Autodesk Fusion 360 part; units mm, degrees
(part 2 of 6)
sketch "Sketch8" plane through (0, 0, 0) normal (0, 1, 0) x (-1, 0, 0)
  line L0 (96.56, 60.325) -> (94.4114, 75.5973)
  line L1 (94.4114, 75.5973) -> (80.5229, 127.4298)
  line L2 (80.5229, 127.4298) -> (-3.2035, 104.9953)
  line L3 (-3.2035, 104.9953) -> (-6.3109, 81.055)
  line L4 (-6.3109, 81.055) -> (-69.625, 81.055)
  line L5 (-69.625, 81.055) -> (-69.625, 62.005)
  line L6 (-69.625, 62.005) -> (-88.675, 62.005)
  line L7 (-88.675, 62.005) -> (-88.675, -58.195)
  line L8 (-88.675, -58.195) -> (-12.475, -58.195)
  line L9 (-12.475, -58.195) -> (-12.475, -67.72)
  line L10 (-12.475, -67.72) -> (6.575, -67.72)
  line L11 (6.575, -67.72) -> (6.575, -75.34)
  line L12 (6.575, -75.34) -> (50.575, -75.34)
  line L13 (50.575, -75.34) -> (50.575, -69.625)
  line L14 (50.575, -69.625) -> (96.56, -69.625)
  line L15 (96.56, -69.625) -> (96.56, 60.325)
  line L16 (17.9, 22.105) -> (1.15, 22.105)
  line L17 (1.15, 22.105) -> (1.15, 38.855)
  line L18 (1.15, 38.855) -> (17.9, 38.855)
  line L19 (17.9, 38.855) -> (17.9, 22.105)
  line L20 (-56, -6.47) -> (-56, 10.28)
  line L21 (-56, 10.28) -> (-39.25, 10.28)
  line L22 (-39.25, 10.28) -> (-39.25, -6.47)
  line L23 (-39.25, -6.47) -> (-56, -6.47)
  line L24 (17.9, -15.995) -> (1.15, -15.995)
  line L25 (1.15, -15.995) -> (1.15, 0.755)
  line L26 (1.15, 0.755) -> (17.9, 0.755)
  line L27 (17.9, 0.755) -> (17.9, -15.995)
  line L28 (-20.2, 50.68) -> (-36.95, 50.68)
  line L29 (-36.95, 50.68) -> (-36.95, 67.43)
  line L30 (-36.95, 67.43) -> (-20.2, 67.43)
  line L31 (-20.2, 67.43) -> (-20.2, 50.68)
  line L32 (75.05, -36.95) -> (58.3, -36.95)
  line L33 (58.3, -36.95) -> (58.3, -20.2)
  line L34 (58.3, -20.2) -> (75.05, -20.2)
  line L35 (75.05, -20.2) -> (75.05, -36.95)
  line L36 (-75.05, -6.47) -> (-75.05, 29.33)
  line L37 (-75.05, 29.33) -> (-58.3, 29.33)
  line L38 (-58.3, 29.33) -> (-58.3, -6.47)
  line L39 (-58.3, -6.47) -> (-75.05, -6.47)
  line L40 (-1.15, -25.52) -> (-17.9, -25.52)
  line L41 (-17.9, -25.52) -> (-17.9, -8.77)
  line L42 (-17.9, -8.77) -> (-1.15, -8.77)
  line L43 (-1.15, -8.77) -> (-1.15, -25.52)
  line L44 (20.2, -61.715) -> (20.2, -44.965)
  line L45 (20.2, -44.965) -> (36.95, -44.965)
  line L46 (36.95, -44.965) -> (36.95, -61.715)
  line L47 (36.95, -61.715) -> (20.2, -61.715)
  line L48 (56, 1.15) -> (39.25, 1.15)
  line L49 (39.25, 1.15) -> (39.25, 17.9)
  line L50 (39.25, 17.9) -> (56, 17.9)
  line L51 (56, 17.9) -> (56, 1.15)
  line L52 (-58.3, -44.57) -> (-75.05, -44.57)
  line L53 (-75.05, -44.57) -> (-75.05, -27.82)
  line L54 (-75.05, -27.82) -> (-58.3, -27.82)
  line L55 (-58.3, -27.82) -> (-58.3, -44.57)
  line L56 (-20.2, -6.47) -> (-36.95, -6.47)
  line L57 (-36.95, -6.47) -> (-36.95, 10.28)
  line L58 (-36.95, 10.28) -> (-20.2, 10.28)
  line L59 (-20.2, 10.28) -> (-20.2, -6.47)
  line L60 (20.2, 14.485) -> (20.2, 31.235)
  line L61 (20.2, 31.235) -> (36.95, 31.235)
  line L62 (36.95, 31.235) -> (36.95, 14.485)
  line L63 (36.95, 14.485) -> (20.2, 14.485)
  line L64 (-1.15, 31.63) -> (-17.9, 31.63)
  line L65 (-17.9, 31.63) -> (-17.9, 48.38)
  line L66 (-17.9, 48.38) -> (-1.15, 48.38)
  line L67 (-1.15, 48.38) -> (-1.15, 31.63)
  line L68 (17.9, -35.045) -> (1.15, -35.045)
  line L69 (1.15, -35.045) -> (1.15, -18.295)
  line L70 (1.15, -18.295) -> (17.9, -18.295)
  line L71 (17.9, -18.295) -> (17.9, -35.045)
  line L72 (56.3587, 69.7865) -> (52.0235, 85.9657)
  line L73 (52.0235, 85.9657) -> (68.2028, 90.3009)
  line L74 (68.2028, 90.3009) -> (72.538, 74.1217)
  line L75 (72.538, 74.1217) -> (56.3587, 69.7865)
  line L76 (1.15, -54.095) -> (1.15, -37.345)
  line L77 (1.15, -37.345) -> (17.9, -37.345)
  line L78 (17.9, -37.345) -> (17.9, -54.095)
  line L79 (17.9, -54.095) -> (1.15, -54.095)
  line L80 (20.2, -4.565) -> (20.2, 12.185)
  line L81 (20.2, 12.185) -> (36.95, 12.185)
  line L82 (36.95, 12.185) -> (36.95, -4.565)
  line L83 (36.95, -4.565) -> (20.2, -4.565)
  line L84 (75.05, 39.25) -> (36.95, 39.25)
  line L85 (36.95, 39.25) -> (36.95, 33.535)
  line L86 (36.95, 33.535) -> (20.2, 33.535)
  line L87 (20.2, 33.535) -> (20.2, 56)
  line L88 (20.2, 56) -> (75.05, 56)
  line L89 (75.05, 56) -> (75.05, 39.25)
  line L90 (17.9, 3.055) -> (1.15, 3.055)
  line L91 (1.15, 3.055) -> (1.15, 19.805)
  line L92 (1.15, 19.805) -> (17.9, 19.805)
  line L93 (17.9, 19.805) -> (17.9, 3.055)
  line L94 (17.9, 41.155) -> (1.15, 41.155)
  line L95 (1.15, 41.155) -> (1.15, 57.905)
  line L96 (1.15, 57.905) -> (17.9, 57.905)
  line L97 (17.9, 57.905) -> (17.9, 41.155)
  line L98 (20.2, -23.615) -> (20.2, -6.865)
  line L99 (20.2, -6.865) -> (36.95, -6.865)
  line L100 (36.95, -6.865) -> (36.95, -23.615)
  line L101 (36.95, -23.615) -> (20.2, -23.615)
  line L102 (-56, -44.57) -> (-56, -27.82)
  line L103 (-56, -27.82) -> (-39.25, -27.82)
  line L104 (-39.25, -27.82) -> (-39.25, -44.57)
  line L105 (-39.25, -44.57) -> (-56, -44.57)
  line L106 (51.4282, 88.1874) -> (47.093, 104.3666)
  line L107 (47.093, 104.3666) -> (63.2723, 108.7018)
  line L108 (63.2723, 108.7018) -> (67.6075, 92.5226)
  line L109 (67.6075, 92.5226) -> (51.4282, 88.1874)
  line L110 (-20.2, 31.63) -> (-36.95, 31.63)
  line L111 (-36.95, 31.63) -> (-36.95, 48.38)
  line L112 (-36.95, 48.38) -> (-20.2, 48.38)
  line L113 (-20.2, 48.38) -> (-20.2, 31.63)
  line L114 (-1.15, -6.47) -> (-17.9, -6.47)
  line L115 (-17.9, -6.47) -> (-17.9, 10.28)
  line L116 (-17.9, 10.28) -> (-1.15, 10.28)
  line L117 (-1.15, 10.28) -> (-1.15, -6.47)
  line L118 (-17.9, -44.57) -> (-17.9, -27.82)
  line L119 (-17.9, -27.82) -> (-1.15, -27.82)
  line L120 (-1.15, -27.82) -> (-1.15, -44.57)
  line L121 (-1.15, -44.57) -> (-17.9, -44.57)
  line L122 (56, -56) -> (39.25, -56)
  line L123 (39.25, -56) -> (39.25, -39.25)
  line L124 (39.25, -39.25) -> (56, -39.25)
  line L125 (56, -39.25) -> (56, -56)
  line L126 (75.05, -17.9) -> (58.3, -17.9)
  line L127 (58.3, -17.9) -> (58.3, -1.15)
  line L128 (58.3, -1.15) -> (75.05, -1.15)
  line L129 (75.05, -1.15) -> (75.05, -17.9)
  line L130 (-20.2, -25.52) -> (-36.95, -25.52)
  line L131 (-36.95, -25.52) -> (-36.95, -8.77)
  line L132 (-36.95, -8.77) -> (-20.2, -8.77)
  line L133 (-20.2, -8.77) -> (-20.2, -25.52)
  line L134 (-58.3, -25.52) -> (-75.05, -25.52)
  line L135 (-75.05, -25.52) -> (-75.05, -8.77)
  line L136 (-75.05, -8.77) -> (-58.3, -8.77)
  line L137 (-58.3, -8.77) -> (-58.3, -25.52)
  line L138 (-20.2, 12.58) -> (-36.95, 12.58)
  line L139 (-36.95, 12.58) -> (-36.95, 29.33)
  line L140 (-36.95, 29.33) -> (-20.2, 29.33)
  line L141 (-20.2, 29.33) -> (-20.2, 12.58)
  line L142 (-56, 50.68) -> (-56, 67.43)
  line L143 (-56, 67.43) -> (-39.25, 67.43)
  line L144 (-39.25, 67.43) -> (-39.25, 50.68)
  line L145 (-39.25, 50.68) -> (-56, 50.68)
  line L146 (37.9578, 64.856) -> (33.6226, 81.0352)
  line L147 (33.6226, 81.0352) -> (49.8019, 85.3704)
  line L148 (49.8019, 85.3704) -> (54.1371, 69.1912)
  line L149 (54.1371, 69.1912) -> (37.9578, 64.856)
  line L150 (-1.15, 12.58) -> (-17.9, 12.58)
  line L151 (-17.9, 12.58) -> (-17.9, 29.33)
  line L152 (-17.9, 29.33) -> (-1.15, 29.33)
  line L153 (-1.15, 29.33) -> (-1.15, 12.58)
  line L154 (-75.05, 31.63) -> (-75.05, 48.38)
  line L155 (-75.05, 48.38) -> (-39.25, 48.38)
  line L156 (-39.25, 48.38) -> (-39.25, 31.63)
  line L157 (-39.25, 31.63) -> (-75.05, 31.63)
  line L158 (56, 20.2) -> (39.25, 20.2)
  line L159 (39.25, 20.2) -> (39.25, 36.95)
  line L160 (39.25, 36.95) -> (56, 36.95)
  line L161 (56, 36.95) -> (56, 20.2)
  line L162 (58.3, -56) -> (58.3, -39.25)
  line L163 (58.3, -39.25) -> (75.05, -39.25)
  line L164 (75.05, -39.25) -> (75.05, -56)
  line L165 (75.05, -56) -> (58.3, -56)
  line L166 (14.6264, 78.3264) -> (10.2912, 94.5056)
  line L167 (10.2912, 94.5056) -> (26.4705, 98.8408)
  line L168 (26.4705, 98.8408) -> (30.8057, 82.6616)
  line L169 (30.8057, 82.6616) -> (14.6264, 78.3264)
  line L170 (33.0273, 83.2569) -> (28.6921, 99.4361)
  line L171 (28.6921, 99.4361) -> (44.8714, 103.7713)
  line L172 (44.8714, 103.7713) -> (49.2066, 87.5921)
  line L173 (49.2066, 87.5921) -> (33.0273, 83.2569)
  line L174 (-56, 12.58) -> (-56, 29.33)
  line L175 (-56, 29.33) -> (-39.25, 29.33)
  line L176 (-39.25, 29.33) -> (-39.25, 12.58)
  line L177 (-39.25, 12.58) -> (-56, 12.58)
  line L178 (56, -36.95) -> (39.25, -36.95)
  line L179 (39.25, -36.95) -> (39.25, -20.2)
  line L180 (39.25, -20.2) -> (56, -20.2)
  line L181 (56, -20.2) -> (56, -36.95)
  line L182 (75.05, 20.2) -> (58.3, 20.2)
  line L183 (58.3, 20.2) -> (58.3, 36.95)
  line L184 (58.3, 36.95) -> (75.05, 36.95)
  line L185 (75.05, 36.95) -> (75.05, 20.2)
  line L186 (-20.2, -44.57) -> (-36.95, -44.57)
  line L187 (-36.95, -44.57) -> (-36.95, -27.82)
  line L188 (-36.95, -27.82) -> (-20.2, -27.82)
  line L189 (-20.2, -27.82) -> (-20.2, -44.57)
  line L190 (75.05, 1.15) -> (58.3, 1.15)
  line L191 (58.3, 1.15) -> (58.3, 17.9)
  line L192 (58.3, 17.9) -> (75.05, 17.9)
  line L193 (75.05, 17.9) -> (75.05, 1.15)
  line L194 (-39.25, -25.52) -> (-56, -25.52)
  line L195 (-56, -25.52) -> (-56, -8.77)
  line L196 (-56, -8.77) -> (-39.25, -8.77)
  line L197 (-39.25, -8.77) -> (-39.25, -25.52)
  line L198 (19.5569, 59.9255) -> (15.2217, 76.1047)
  line L199 (15.2217, 76.1047) -> (31.401, 80.4399)
  line L200 (31.401, 80.4399) -> (35.7362, 64.2607)
  line L201 (35.7362, 64.2607) -> (19.5569, 59.9255)
  line L202 (20.2, -42.665) -> (20.2, -25.915)
  line L203 (20.2, -25.915) -> (36.95, -25.915)
  line L204 (36.95, -25.915) -> (36.95, -42.665)
  line L205 (36.95, -42.665) -> (20.2, -42.665)
  line L206 (56, -17.9) -> (39.25, -17.9)
  line L207 (39.25, -17.9) -> (39.25, -1.15)
  line L208 (39.25, -1.15) -> (56, -1.15)
  line L209 (56, -1.15) -> (56, -17.9)
  line L210 (-1.15, 50.68) -> (-17.9, 50.68)
  line L211 (-17.9, 50.68) -> (-17.9, 67.43)
  line L212 (-17.9, 67.43) -> (-1.15, 67.43)
  line L213 (-1.15, 67.43) -> (-1.15, 50.68)
  line L214 (65.8355, 113.1415) -> (5.7914, 97.0528)
  line L215 (2.475, 71.055) -> (-59.625, 71.055)
  line L216 (-59.625, 71.055) -> (-59.625, 52.005)
  line L217 (-59.625, 52.005) -> (-78.675, 52.005)
  line L218 (-78.675, 52.005) -> (-78.675, -48.195)
  line L219 (-78.675, -48.195) -> (-2.475, -48.195)
  line L220 (-2.475, -48.195) -> (-2.475, -57.72)
  line L221 (-2.475, -57.72) -> (16.575, -57.72)
  line L222 (16.575, -57.72) -> (16.575, -65.34)
  line L223 (16.575, -65.34) -> (40.575, -65.34)
  line L224 (40.575, -65.34) -> (40.575, -59.625)
  line L225 (40.575, -59.625) -> (78.8, -59.625)
  line L226 (1.15, 57.905) -> (1.15, 61.655) construction
  line L227 (1.15, 61.655) -> (15.25, 61.655) construction
  line L228 (2.475, 71.055) -> (2.475, 61.655)
  line L229 (5.7914, 97.0528) -> (15.25, 61.655)
  line L230 (15.25, 61.655) -> (2.475, 61.655)
  line L231 (72.538, 74.1217) -> (73.5085, 70.4995) construction
  line L232 (33.391, 56) -> (33.391, 59.75) construction
  line L233 (32.4204, 63.3722) -> (33.391, 59.75) construction
  line L234 (73.4519, 115.1823) -> (65.8355, 113.1415) construction
  line L235 (65.8355, 113.1415) -> (76.9777, 71.5584)
  line L236 (76.9777, 71.5584) -> (33.391, 59.75)
  line L237 (75.05, 56) -> (78.8, 56) construction
  line L238 (78.8, 56) -> (78.8, 59.75) construction
  line L239 (33.391, 59.75) -> (78.8, 59.75)
  line L240 (78.8, 59.75) -> (78.8, -59.625)
  dimension "d208" = 3.75
  dimension "d209" = 14.1
  dimension "d210" = 3.75
  dimension "d211" = 3.75
  dimension "d212" = 3.75
  dimension "d213" = 7.885
  dimension "d214" = 43.05
  dimension "d215" = 3.75
  dimension "d216" = 3.75
  dimension "d217" = 10
  dimension "d218" = 10
  dimension "d219" = 10
  dimension "d220" = 10
  dimension "d221" = 10
  dimension "d222" = 10
  dimension "d223" = 10
  dimension "d224" = 10
  dimension "d225" = 10
  dimension "d226" = 10
  dimension "d227" = 10
  dimension "d228" = 10
  constraint coincident L95.end L96.start
  constraint perpendicular L96 L226
  constraint perpendicular L95 L227
  constraint coincident L227 L228.end
  constraint perpendicular L227 L228
  constraint coincident L74.end L75.start
  constraint perpendicular L75 L231
  constraint coincident L88 L232.start
  constraint perpendicular L88 L232
  constraint coincident L201 L233.start
  constraint perpendicular L201 L233
  constraint coincident L232.end L233.end
  constraint perpendicular L234 L235
  constraint coincident L88.end L89.start
  constraint perpendicular L89 L237
  constraint perpendicular L237 L238
  constraint perpendicular L225 L240
  measures "d208" distance of L95.end L226.end
  measures "d209" distance of L226.end L227.end
  measures "d210" distance of L74.end L231.end
  measures "d211" distance of L232.start L232.end
  measures "d212" distance of L233.start L232.end
  measures "d213" distance of L234.start L214.start
  measures "d214" distance of L214.start L235.end
  measures "d215" distance of L88.end L237.end
  measures "d216" distance of L237.end L238.end
  measures "d217" distance of L2 L214
  measures "d218" distance of L4 L215
  measures "d219" distance of L5 L216
  measures "d220" distance of L6 L217
  measures "d221" distance of L7 L218
  measures "d222" distance of L8 L219
  measures "d223" distance of L9 L220
  measures "d224" distance of L10 L221
  measures "d225" distance of L11 L222
  measures "d226" distance of L12 L223
  measures "d227" distance of L13 L224
  measures "d228" distance of L14 L225
extrude "Extrude5" add sketch "Sketch8" along normal blind 2.5 contours L0 L1 L2 L3 L4 L5 L6 L7 L8 L9 L10 L11 L12 L13 L14 L15
fillet "Fillet1" radius 1.5 19 edges at (-33.391, 1.25, 59.75) (-76.9777, 1.25, 71.5584) (-78.8, 1.25, 59.75) (-65.8355, 1.25, 113.1415) (-15.25, 1.25, 61.655) (-2.475, 1.25, 61.655) (-2.475, 1.25, 71.055) (-5.7914, 1.25, 97.0528) (59.625, 1.25, 71.055) (59.625, 1.25, 52.005) (78.675, 1.25, 52.005) (78.675, 1.25, -48.195) (2.475, 1.25, -48.195) (2.475, 1.25, -57.72) (-16.575, 1.25, -57.72) (-40.575, 1.25, -65.34) (-16.575, 1.25, -65.34) (-40.575, 1.25, -59.625) (-78.8, 1.25, -59.625)
fillet "Fillet2" radius 1 38 edges at (-43.1771, 2.5, 61.0522) (-60.982, 2.5, 59.75) (-78.3607, 2.5, 59.3107) (-78.8, 2.5, 0.0625) (-78.3607, 2.5, -59.1857) (-59.6875, 2.5, -59.625) (-41.0143, 2.5, -60.0643) (-40.575, 2.5, -62.4825) (-40.1357, 2.5, -64.9007) (-28.575, 2.5, -65.34) (-17.0143, 2.5, -64.9007) (-16.575, 2.5, -61.53) (-16.1357, 2.5, -58.1593) (-7.05, 2.5, -57.72) (2.0357, 2.5, -57.2807) (2.475, 2.5, -52.9575) (2.9143, 2.5, -48.6343) (40.575, 2.5, -48.195) (78.2357, 2.5, -47.7557) (78.675, 2.5, 1.905) (78.2357, 2.5, 51.5657) (69.15, 2.5, 52.005) (60.0643, 2.5, 52.4443) (59.625, 2.5, 61.53) (59.1857, 2.5, 70.6157) (28.575, 2.5, 71.055) (-2.0357, 2.5, 70.6157) (-2.475, 2.5, 66.355) (-2.9143, 2.5, 62.0943) (-8.6358, 2.5, 61.655) (-14.4863, 2.5, 62.2414) (-10.462, 2.5, 79.5734) (-6.3287, 2.5, 96.7423) (-35.813, 2.5, 105.097) (-65.5249, 2.5, 112.6035) (-71.4072, 2.5, 92.348) (-76.4417, 2.5, 71.8669) (-59.9028, 2.5, 66.9325)
sketch "Sketch9" plane through (0, -4, 0) normal (0, -1, 0) x (1, 0, 0)
  line L0 (-96.56, -49.625) -> (-86.56, -49.625)
  line L1 (-86.56, -49.625) -> (-86.56, 59.625)
  line L2 (-86.56, 59.625) -> (-84.594, 73.5992)
  line L3 (-84.594, 73.5992) -> (-76.04, 105.5231)
  line L4 (-76.04, 105.5231) -> (-85.6993, 108.1113)
  line L5 (-85.6993, 108.1113) -> (-94.4114, 75.5973)
  line L6 (-94.4114, 75.5973) -> (-96.56, 60.325)
  line L7 (-96.56, 60.325) -> (-96.56, -49.625)
  line L8 (-84.594, 73.5992) -> (-94.2533, 76.1874) construction
  line L9 (-89.4236, 74.8933) -> (-80.8697, 106.8172) construction
  circle A0 centre (-85.1466, 90.8552) radius 1.25
  line L10 (-86.56, 59.625) -> (-96.56, 59.625) construction
  line L11 (-91.56, -49.625) -> (-91.56, 59.625) construction
  line L12 (-91.56, -49.625) -> (-145.9994, 68.1019) construction
  circle A1 centre (-91.56, -49.625) radius 30 construction
  circle A2 centre (-104.1516, -22.3954) radius 30 construction
  circle A3 centre (-116.7431, 4.8343) radius 30 construction
  circle A4 centre (-129.3347, 32.0639) radius 30 construction
  line L13 (-129.3347, 32.0639) -> (-91.56, 59.625) construction
  line L14 (-116.7431, 4.8343) -> (-105.0997, 49.7462) construction
  circle A5 centre (-104.1516, -22.3954) radius 46.3967 construction
  circle A6 centre (-91.56, -49.625) radius 46.3967 construction
  line L15 (-91.56, -49.625) -> (-133.6722, -69.0986) construction
  line L16 (-104.1516, -22.3954) -> (-150.1994, -28.0744) construction
  line L17 (-116.7431, 4.8343) -> (-92.5081, 22.5166) construction
  line L18 (-92.5081, 22.5166) -> (-80.406, 31.3465) construction
  line L19 (-104.1516, -22.3954) -> (-79.9165, -4.7131) construction
  circle A7 centre (-91.56, -13.2083) radius 1.25
  circle A8 centre (-91.56, 23.2083) radius 1.25
  dimension "d235" = 2.5
  dimension "d236" = 60
  dimension "d237" = 2.5
  dimension "d238" = 2.5
  constraint coincident L2.end L3.start
  constraint coincident L5 L8.end
  constraint perpendicular L5 L8
  constraint midpoint L8 L9.start
  constraint midpoint L4 L9.end
  constraint midpoint L9 A0.centre
  constraint coincident L1.end L2.start
  constraint coincident L7 L10.end
  constraint perpendicular L7 L10
  constraint midpoint L0 L11.start
  constraint midpoint L10 L11.end
  constraint coincident L11.start L12.start
  constraint coincident A1 A2.centre
  constraint coincident L12 A2.centre
  constraint coincident L11.start A2
  constraint coincident A2 A3.centre
  constraint coincident L12 A3.centre
  constraint coincident A2.centre A3
  constraint coincident A3 A4.centre
  constraint coincident L12 A4.centre
  constraint coincident A3.centre A4
  constraint coincident A4.centre L13.start
  constraint coincident A3.centre L14.start
  constraint coincident A4 L14.end
  constraint coincident L13 L14.end
  constraint concentric A2 A5
  constraint coincident A6 L15.end
  constraint tangent A2 L15
  constraint coincident A2.centre A5.centre
  constraint coincident A5 L16.end
  constraint equal L14 L15
  constraint equal L14 L16
  constraint coincident A3 L17.end
  constraint coincident A5 L17.end
  constraint perpendicular A3 L18
  constraint coincident A6 L19.end
  constraint coincident A2 L19.end
  constraint coincident L19 A7.centre
  constraint coincident L11 A7.centre
  constraint coincident L18 A8.centre
  constraint coincident L11 A8.centre
  measures "d235" diameter of A0
  measures "d236" diameter of A1
  measures "d237" diameter of A7
  measures "d238" diameter of A8
sketch "Sketch10" plane through (0, -4, 0) normal (0, -1, 0) x (1, 0, 0)
  line L0 (78.675, -38.195) -> (88.675, -38.195)
  line L1 (88.675, -38.195) -> (88.675, 52.005)
  line L2 (88.675, 52.005) -> (78.675, 52.005)
  line L3 (78.675, 52.005) -> (78.675, -38.195)
  line L4 (83.675, -38.195) -> (83.675, 52.005) construction
  line L5 (83.675, -38.195) -> (131.5934, 61.3781) construction
  circle A0 centre (83.675, -38.195) radius 30 construction
  circle A1 centre (96.6841, -11.1624) radius 30 construction
  circle A2 centre (109.6933, 15.8702) radius 30 construction
  circle A3 centre (122.7024, 42.9029) radius 30 construction
  line L6 (122.7024, 42.9029) -> (83.675, 52.005) construction
  line L7 (109.6933, 15.8702) -> (93.4865, 49.7167) construction
  circle A4 centre (96.6841, -11.1624) radius 37.5266 construction
  circle A5 centre (83.675, -38.195) radius 37.5266 construction
  line L8 (83.675, -38.195) -> (115.208, -58.5399) construction
  line L9 (96.6841, -11.1624) -> (128.2172, -31.5072) construction
  line L10 (80.4773, 22.6841) -> (109.6933, 15.8702) construction
  line L11 (96.6841, -11.1624) -> (67.4682, -4.3485) construction
  circle A6 centre (83.675, -8.1283) radius 1.25
  circle A7 centre (83.675, 21.9383) radius 1.25
  dimension "d239" = 60
  dimension "d240" = 2.5
  dimension "d241" = 2.5
  constraint midpoint L0 L4.start
  constraint midpoint L2 L4.end
  constraint coincident L4.start L5.start
  constraint coincident A0 A1.centre
  constraint coincident L5 A1.centre
  constraint coincident L4.start A1
  constraint coincident A1 A2.centre
  constraint coincident L5 A2.centre
  constraint coincident A1.centre A2
  constraint coincident A2 A3.centre
  constraint coincident L5 A3.centre
  constraint coincident A2.centre A3
  constraint coincident A3.centre L6.start
  constraint coincident A2.centre L7.start
  constraint coincident L6 L7.end
  constraint coincident A3 L7.end
  constraint concentric A1 A4
  constraint concentric A0 A5
  constraint coincident A5 L8.end
  constraint coincident A1.centre A4.centre
  constraint coincident A4 L9.end
  constraint parallel L8 L9
  constraint equal L7 L9
  constraint equal L7 L8
  constraint coincident A2 L10.start
  constraint coincident A4 L10.start
  constraint coincident A5 L11.end
  constraint coincident A1 L11.end
  constraint coincident L11 A6.centre
  constraint coincident L4 A6.centre
  constraint coincident L10 A7.centre
  constraint coincident L4 A7.centre
  measures "d239" diameter of A0
  measures "d240" diameter of A6
  measures "d241" diameter of A7
sketch "Sketch11" plane through (0, -4, 0) normal (0, -1, 0) x (1, 0, 0)
  line L0 (-76.56, -59.625) -> (-76.56, -69.625)
  line L1 (-76.56, -69.625) -> (-50.575, -69.625)
  line L2 (-50.575, -69.625) -> (-50.575, -75.34)
  line L3 (-50.575, -75.34) -> (-6.575, -75.34)
  line L4 (-6.575, -75.34) -> (-6.575, -67.72)
  line L5 (-6.575, -67.72) -> (12.475, -67.72)
  line L6 (12.475, -67.72) -> (12.475, -58.195)
  line L7 (12.475, -58.195) -> (68.675, -58.195)
  line L8 (68.675, -58.195) -> (68.675, -48.195)
  line L9 (68.675, -48.195) -> (2.475, -48.195)
  line L10 (2.475, -48.195) -> (2.475, -57.72)
  line L11 (2.475, -57.72) -> (-16.575, -57.72)
  line L12 (-16.575, -57.72) -> (-16.575, -65.34)
  line L13 (-16.575, -65.34) -> (-40.575, -65.34)
  line L14 (-40.575, -65.34) -> (-40.575, -59.625)
  line L15 (-40.575, -59.625) -> (-76.56, -59.625)
  line L16 (12.475, -58.195) -> (2.475, -48.195) construction
  line L17 (7.475, -53.195) -> (68.675, -53.195) construction
  circle A0 centre (38.075, -53.195) radius 1.25
  line L18 (-28.575, -75.34) -> (-28.575, -65.34) construction
  circle A1 centre (-28.575, -70.34) radius 1.25
  dimension "d242" = 2.5
  dimension "d243" = 2.5
  constraint coincident L6.end L7.start
  constraint coincident L9.end L10.start
  constraint midpoint L16 L17.start
  constraint midpoint L8 L17.end
  constraint midpoint L17 A0.centre
  constraint midpoint L3 L18.start
  constraint midpoint L13 L18.end
  constraint midpoint L18 A1.centre
  measures "d242" diameter of A0
  measures "d243" diameter of A1
sketch "Sketch12" plane through (0, -4, 0) normal (0, -1, 0) x (1, 0, 0)
  line L0 (-61.2044, 122.2534) -> (-63.7926, 112.5941)
  line L1 (-63.7926, 112.5941) -> (-5.8515, 97.0689)
  line L2 (-5.8515, 97.0689) -> (-2.475, 71.055)
  line L3 (-2.475, 71.055) -> (59.625, 71.055)
  line L4 (59.625, 71.055) -> (59.625, 81.055)
  line L5 (59.625, 81.055) -> (6.3109, 81.055)
  line L6 (6.3109, 81.055) -> (3.2035, 104.9953)
  line L7 (3.2035, 104.9953) -> (-61.2044, 122.2534)
  line L8 (-2.475, 71.055) -> (6.3109, 81.055) construction
  line L9 (-5.8515, 97.0689) -> (3.2035, 104.9953) construction
  line L10 (-34.8293, 104.8334) -> (-32.2411, 114.4927) construction
  line L11 (4.7572, 93.0252) -> (-4.1633, 84.0619) construction
  line L12 (0.297, 88.5436) -> (-33.5352, 109.6631) construction
  line L13 (-16.6191, 99.1033) -> (3.2035, 104.9953) construction
  line L14 (-6.7078, 102.0493) -> (-1.324, 101.0321) construction
  line L15 (-6.7078, 102.0493) -> (-3.868, 98.8052) construction
  line L16 (-3.868, 98.8052) -> (-1.324, 101.0321) construction
  circle A0 centre (-2.596, 99.9186) radius 1.25
  line L17 (1.918, 76.055) -> (59.625, 76.055) construction
  circle A1 centre (30.7715, 76.055) radius 1.25
  line L18 (-34.8293, 104.8334) -> (-5.8515, 97.0689) construction
  dimension "d244" = 2.5
  dimension "d245" = 2.5
  dimension "d260" = 30
  constraint coincident L2.end L3.start
  constraint coincident L5.end L6.start
  constraint coincident L1.end L2.start
  constraint coincident L6.end L7.start
  constraint coincident L7 L10.end
  constraint perpendicular L7 L10
  constraint midpoint L6 L11.start
  constraint midpoint L2 L11.end
  constraint midpoint L11 L12.start
  constraint midpoint L10 L12.end
  constraint midpoint L12 L13.start
  constraint midpoint L13 L14.start
  constraint midpoint L9 L14.end
  constraint coincident L9 L15.end
  constraint perpendicular L9 L15
  constraint midpoint L16 A0.centre
  constraint midpoint L8 L17.start
  constraint midpoint L4 L17.end
  constraint midpoint L17 A1.centre
  constraint perpendicular L10 L18
  measures "d244" diameter of A0
  measures "d245" diameter of A1
  measures "d260" distance of L1.end L10.start
extrude "Extrude6" add sketch "Sketch12" sketch "Sketch9" sketch "Sketch11" sketch "Sketch10" along normal blind 5 contours A0 | A1 of sketch 2 contours A0 | A7 | A8 of sketch 3 contours A0 | A1 of sketch 4 contours A6 | A7
fillet "Fillet3" radius 1.25 9 edges at (29.6061, -9, 75.603) (-3.7614, -9, 99.4666) (-86.3121, -9, 90.4032) (-92.7254, -9, 22.7563) (-92.7254, -9, -13.6604) (-29.7404, -9, -70.792) (36.9096, -9, -53.647) (82.5096, -9, -8.5804) (82.5096, -9, 21.4863)
fillet "Fillet4" radius 1 198 edges at (-72.538, -0.75, 74.1217) (-54.1371, -0.75, 69.1912) (-35.7362, -0.75, 64.2607) (-30.8057, -0.75, 82.6616) (-49.2066, -0.75, 87.5921) (-67.6075, -0.75, 92.5226) (-56.3587, -0.75, 69.7865) (-51.4282, -0.75, 88.1874) (-33.0273, -0.75, 83.2569) (-19.5569, -0.75, 59.9255) (-37.9578, -0.75, 64.856) (-14.6264, -0.75, 78.3264) (-10.2912, -0.75, 94.5056) (-47.093, -0.75, 104.3666) (-28.6921, -0.75, 99.4361) (-52.0235, -0.75, 85.9657) (-33.6226, -0.75, 81.0352) (-15.2217, -0.75, 76.1047) (-26.4705, -0.75, 98.8408) (-31.401, -0.75, 80.4399) (-49.8019, -0.75, 85.3704) (-44.8714, -0.75, 103.7713) (-63.2723, -0.75, 108.7018) (-68.2028, -0.75, 90.3009) (-20.2, -0.75, 56) (-20.2, -0.75, 33.535) (-36.95, -0.75, 39.25) (-36.95, -0.75, 33.535) (-75.05, -0.75, 39.25) (-75.05, -0.75, 56) (-75.05, -0.75, 20.2) (-75.05, -0.75, 1.15) (-75.05, -0.75, -17.9) (-75.05, -0.75, -36.95) (-56, -0.75, -36.95) (-56, -0.75, -17.9) (-56, -0.75, 1.15) (-56, -0.75, 20.2) (-75.05, -0.75, -56) (-56, -0.75, -56) (-36.95, -0.75, -61.715) (-17.9, -0.75, -54.095) (-17.9, -0.75, -35.045) (-36.95, -0.75, -42.665) (-17.9, -0.75, -15.995) (-36.95, -0.75, -23.615) (-36.95, -0.75, -4.565) (-36.95, -0.75, 14.485) (-17.9, -0.75, 22.105) (-17.9, -0.75, 3.055) (-17.9, -0.75, 41.155) (1.15, -0.75, 50.68) (39.25, -0.75, 50.68) (20.2, -0.75, 50.68) (39.25, -0.75, 31.63) (20.2, -0.75, 31.63) (1.15, -0.75, 31.63) (1.15, -0.75, 12.58) (20.2, -0.75, 12.58) (39.25, -0.75, 12.58) (58.3, -0.75, -6.47) (39.25, -0.75, -6.47) (20.2, -0.75, -6.47) (1.15, -0.75, -6.47) (1.15, -0.75, -25.52) (1.15, -0.75, -44.57) (20.2, -0.75, -44.57) (20.2, -0.75, -25.52) (39.25, -0.75, -25.52) (39.25, -0.75, -44.57) (58.3, -0.75, -44.57) (58.3, -0.75, -25.52) (-39.25, -0.75, 20.2) (-58.3, -0.75, 20.2) (-39.25, -0.75, 1.15) (-58.3, -0.75, 1.15) (-20.2, -0.75, 14.485) (-20.2, -0.75, -4.565) (-20.2, -0.75, -23.615) (-39.25, -0.75, -17.9) (-58.3, -0.75, -17.9) (-58.3, -0.75, -36.95) (-39.25, -0.75, -36.95) (-20.2, -0.75, -42.665) (-20.2, -0.75, -61.715) (-39.25, -0.75, -56) (-58.3, -0.75, -56) (-1.15, -0.75, -54.095) (17.9, -0.75, -44.57) (-1.15, -0.75, -35.045) (17.9, -0.75, -25.52) (-1.15, -0.75, -15.995) (17.9, -0.75, -6.47) (-1.15, -0.75, 3.055) (17.9, -0.75, 12.58) (-1.15, -0.75, 22.105) (17.9, -0.75, 31.63) (-1.15, -0.75, 41.155) (17.9, -0.75, 50.68) (36.95, -0.75, 50.68) (56, -0.75, 50.68) (75.05, -0.75, 31.63) (36.95, -0.75, 31.63) (56, -0.75, 12.58) (36.95, -0.75, 12.58) (75.05, -0.75, -6.47) (56, -0.75, -6.47) (36.95, -0.75, -6.47) (36.95, -0.75, -25.52) (56, -0.75, -25.52) (75.05, -0.75, -25.52) (75.05, -0.75, -44.57) (56, -0.75, -44.57) (36.95, -0.75, -44.57) (75.05, -0.75, -27.82) (56, -0.75, -27.82) (36.95, -0.75, -27.82) (36.95, -0.75, -8.77) (56, -0.75, -8.77) (75.05, -0.75, -8.77) (75.05, -0.75, 29.33) (56, -0.75, 10.28) (56, -0.75, 29.33) (36.95, -0.75, 29.33) (36.95, -0.75, 10.28) (17.9, -0.75, -27.82) (17.9, -0.75, -8.77) (17.9, -0.75, 10.28) (17.9, -0.75, 29.33) (36.95, -0.75, 48.38) (75.05, -0.75, 48.38) (56, -0.75, 67.43) (36.95, -0.75, 67.43) (17.9, -0.75, 67.43) (17.9, -0.75, 48.38) (-1.15, -0.75, 57.905) (-1.15, -0.75, 38.855) (-1.15, -0.75, 19.805) (-1.15, -0.75, 0.755) (-1.15, -0.75, -18.295) (-1.15, -0.75, -37.345) (-20.2, -0.75, -44.965) (-20.2, -0.75, -25.915) (-20.2, -0.75, -6.865) (-20.2, -0.75, 12.185) (-20.2, -0.75, 31.235) (-39.25, -0.75, 36.95) (-39.25, -0.75, 17.9) (-58.3, -0.75, 36.95) (-58.3, -0.75, 17.9) (-39.25, -0.75, -1.15) (-58.3, -0.75, -1.15) (-58.3, -0.75, -20.2) (-39.25, -0.75, -20.2) (-39.25, -0.75, -39.25) (-58.3, -0.75, -39.25) (58.3, -0.75, -27.82) (58.3, -0.75, -8.77) (39.25, -0.75, -8.77) (39.25, -0.75, -27.82) (20.2, -0.75, -8.77) (20.2, -0.75, -27.82) (1.15, -0.75, -8.77) (1.15, -0.75, -27.82) (1.15, -0.75, 10.28) (20.2, -0.75, 10.28) (39.25, -0.75, 10.28) (58.3, -0.75, 29.33) (39.25, -0.75, 29.33) (20.2, -0.75, 29.33) (1.15, -0.75, 29.33) (1.15, -0.75, 48.38) (20.2, -0.75, 48.38) (39.25, -0.75, 48.38) (39.25, -0.75, 67.43) (20.2, -0.75, 67.43) (1.15, -0.75, 67.43) (-17.9, -0.75, 57.905) (-17.9, -0.75, 38.855) (-36.95, -0.75, 31.235) (-17.9, -0.75, 19.805) (-36.95, -0.75, 12.185) (-17.9, -0.75, 0.755) (-36.95, -0.75, -6.865) (-17.9, -0.75, -18.295) (-36.95, -0.75, -25.915) (-17.9, -0.75, -37.345) (-36.95, -0.75, -44.965) (-56, -0.75, -39.25) (-56, -0.75, -20.2) (-75.05, -0.75, -20.2) (-75.05, -0.75, -39.25) (-56, -0.75, -1.15) (-75.05, -0.75, -1.15) (-56, -0.75, 17.9) (-56, -0.75, 36.95) (-75.05, -0.75, 36.95) (-75.05, -0.75, 17.9)
fillet "Fillet5" radius 2.5 14 edges at (-80.5229, -2.35, 127.4298) (-96.56, -2.35, -69.625) (-50.575, -0.75, -69.625) (-50.575, -0.75, -75.34) (-6.575, -0.75, -75.34) (12.475, -0.75, -67.72) (12.475, -0.75, -58.195) (88.675, -2.35, -58.195) (-6.575, -0.75, -67.72) (3.2035, -0.75, 104.9953) (6.3109, -0.75, 81.055) (69.625, -2.35, 81.055) (69.625, -2.35, 62.005) (88.675, -2.35, 62.005)
fillet "Fillet6" radius 120 2 edges at (-96.56, -0.75, 60.325) (-94.4114, -0.75, 75.5973)
fillet "Fillet7" radius 0.5 30 edges at (2.8209, 2.5, 104.6604) (4.7236, 2.5, 93.2844) (6.8573, 2.5, 81.6769) (37.8162, 2.5, 81.055) (68.8928, 2.5, 80.3228) (69.625, 2.5, 71.53) (70.3572, 2.5, 62.7372) (79.15, 2.5, 62.005) (87.9428, 2.5, 61.2728) (88.675, 2.5, 1.905) (87.9428, 2.5, -57.4628) (50.575, 2.5, -58.195) (13.2072, 2.5, -58.9272) (12.475, 2.5, -62.9575) (11.7428, 2.5, -66.9878) (2.95, 2.5, -67.72) (-5.8428, 2.5, -68.4522) (-6.575, 2.5, -71.53) (-7.3072, 2.5, -74.6078) (-28.575, 2.5, -75.34) (-49.8428, 2.5, -74.6078) (-50.575, 2.5, -72.4825) (-51.3072, 2.5, -70.3572) (-73.5675, 2.5, -69.625) (-95.8278, 2.5, -68.8928) (-96.56, 2.5, -7.6724) (-95.5334, 2.5, 67.4434) (-86.8205, 2.5, 103.9267) (-80.0051, 2.5, 126.533) (-38.2606, 2.5, 116.1056)
equation "sw_size_Ref_Ref = 19.05 mm"
equation "sw_cut_size_Ref_Ref = 14 mm"
equation "sw_cut_space_Ref_Ref = sw_size_Ref_Ref - sw_cut_size_Ref_Ref"
equation "stab_cut_length_Ref_Ref = 6 mm"
equation "stab_cut_height_Ref_Ref = 12.5 mm"
equation "stabw_length_Ref_Ref = 12 mm" comment "Length of the stabilizer wire per unit (e.g. a 2u stabilizer will be stabilizer_wire_length * 2)"
equation "stabw_height_Ref_Ref = 2.5 mm"
equation "stabw_cut_length_Ref_Ref = 1.7 mm"
equation "stabw_cut_height_Ref_Ref = 1 mm"
equation "plt_thickness_Ref_Ref = 1.5 mm"
equation "plt_fillet_Ref_Ref = 0.25 mm"
equation "pcb_thickness_Ref_Ref = 1.6 mm"
equation "m2scr_diameter_Ref_Ref = 2.05 mm"
equation "mtscr_head_diameter_Ref_Ref = 3.5 mm"
equation "mtscr_head_width_Ref_Ref = 0.5 mm"
equation "ctrl_length_Ref_Ref = 33 mm"
equation "ctrl_height_Ref_Ref = 18 mm"
equation "ctrl_width_Ref_Ref = 1.7 mm"
equation "usbc_length_Ref_Ref = 8.34 mm"
equation "usbc_height_Ref_Ref = 2.56 mm"
equation "bat_length_Ref_Ref = 50 mm"
equation "bat_height_Ref_Ref = 34 mm"
equation "bat_width_Ref_Ref = 5 mm"
equation "bat_clearance_Ref_Ref = 3 mm"
equation "key_size_Ref_Ref = 16.5 mm"
equation "key_clearance_Ref_Ref = 0.25 mm"
equation "key_space_Ref_Ref = sw_size_Ref_Ref - ( key_size_Ref_Ref + key_clearance_Ref_Ref )"
equation "key_fillet_Ref_Ref = 1 mm"
equation "thrins_diameter_Ref_Ref = 3.5 mm"
equation "thrins_depth_Ref_Ref = 2.5 mm"
equation "top_inner_thickness_Ref_Ref = 1.5 mm"
equation "plt_up_clearance_Ref_Ref = 4.9 mm"
equation "alignh_diameter_Ref_Ref = 2.5 mm"
equation "alignh_height_Ref_Ref = 5 mm"
equation "case_border_width_Ref_Ref = 10 mm"
equation "col_mid_offset_Ref_Ref = 0.3 * sw_size_Ref_Ref"
equation "col_ring_offset_Ref_Ref = 0.4 * sw_size_Ref_Ref"
equation "col_pinky_offset_Ref_Ref = 0.5 * sw_size_Ref_Ref"
equation "stab_vert_offset_Ref_Ref = 0.6 mm"
equation "stabw_cut_offset_Ref_Ref = 0.835 mm"
equation "plt_border_width_Ref_Ref = 2.475 mm"
equation "case_top_thickness_Ref_Ref = 4 mm"
equation "top_align_mark_length_Ref_Ref = 10 mm"
equation "pcb_clearance_Ref_Ref = 8.5 mm"
equation "case_bot_min_thickness_Ref_Ref = 3 mm"
equation "case_max_length_Ref_Ref = max(7 * sw_size_Ref_Ref + plt_border_width_Ref_Ref * 2 + case_border_width_Ref_Ref * 2; 8 * sw_size_Ref_Ref + ( plt_border_width_Ref_Ref + case_border_width_Ref_Ref ) * 2 + 7.885 mm)"
equation "case_bot_angle_Ref_Ref = 2.75 deg"
equation "case_bot_max_thickness_Ref_Ref = case_max_length_Ref_Ref / tan(90 deg - case_bot_angle_Ref_Ref) + case_bot_min_thickness_Ref_Ref"
equation "ctrl_socket_height_Ref_Ref = 4.191 mm"
equation "bat_wall_thickness_Ref_Ref = 2.5 mm"
equation "bat_offset_Ref_Ref = 25 mm + bat_wall_thickness_Ref_Ref + bat_length_Ref_Ref * 0.5"
equation "sw_hotswap_clearance_Ref_Ref = 1.9 mm"
equation "case_side_fillet_Ref_Ref = 2.5 mm"
equation "case_top_fillet_Ref_Ref = 0.5 mm"
equation "case_top_inner_border_side_fillet_Ref_Ref = 1.5 mm"
equation "case_top_inner_border_top_fillet_Ref_Ref = 1 mm"
equation "usbc_contour_height_Ref_Ref = 4.5 mm"
equation "usbc_contour_length_Ref_Ref = 12 mm"
equation "assemblyscr_head_diameter_Ref_Ref = 4.15 mm"
equation "assemblyscr_head_width_Ref_Ref = 0.85 mm"
equation "rf_diameter_Ref_Ref = 10 mm"
equation "rf_width_Ref_Ref = 0.5 mm"
equation "rf_voffset_Ref_Ref = case_border_width_Ref_Ref + 10 mm"
equation "rf_hoffset_Ref_Ref = case_border_width_Ref_Ref + 15 mm"
equation "ctrl_extension_width_Ref = 7.885 mm"
equation "d67 = sw_size_Ref_Ref * 6"
equation "d68 = sw_size_Ref_Ref * 2"
equation "d69 = col_mid_offset_Ref_Ref"
equation "d70 = sw_size_Ref_Ref"
equation "d71 = col_ring_offset_Ref_Ref"
equation "d72 = sw_size_Ref_Ref"
equation "d73 = col_pinky_offset_Ref_Ref"
equation "d74 = sw_size_Ref_Ref"
equation "d75 = sw_size_Ref_Ref"
equation "d76 = sw_size_Ref_Ref"
equation "d77 = sw_size_Ref_Ref * 5"
equation "d78 = sw_size_Ref_Ref - col_ring_offset_Ref_Ref"
equation "d79 = sw_size_Ref_Ref * 4"
equation "d80 = sw_size_Ref_Ref - col_pinky_offset_Ref_Ref"
equation "d81 = sw_size_Ref_Ref * 5"
equation "d82 = sw_size_Ref_Ref"
equation "d83 = sw_size_Ref_Ref"
equation "d84 = sw_size_Ref_Ref * 6"
equation "d85 = sw_size_Ref_Ref * 2"
equation "d86 = sw_size_Ref_Ref"
equation "d87 = sw_size_Ref_Ref"
equation "d88 = sw_size_Ref_Ref"
equation "d89 = sw_size_Ref_Ref"
equation "d90 = sw_size_Ref_Ref * 2"
equation "d91 = plt_border_width_Ref_Ref + ctrl_extension_width_Ref"
equation "d92 = plt_border_width_Ref_Ref"
equation "d93 = plt_border_width_Ref_Ref"
equation "d94 = plt_border_width_Ref_Ref"
equation "d95 = plt_border_width_Ref_Ref"
equation "d96 = plt_border_width_Ref_Ref"
equation "d97 = plt_border_width_Ref_Ref"
equation "d98 = plt_border_width_Ref_Ref"
equation "d99 = plt_border_width_Ref_Ref"
equation "d100 = plt_border_width_Ref_Ref"
equation "d101 = plt_border_width_Ref_Ref"
equation "d102 = plt_border_width_Ref_Ref"
equation "d103 = plt_border_width_Ref_Ref"
equation "d104 = plt_border_width_Ref_Ref"
equation "d105 = plt_border_width_Ref_Ref"
equation "d106 = plt_border_width_Ref_Ref"
equation "d107 = plt_border_width_Ref_Ref"
equation "d108 = plt_border_width_Ref_Ref"
equation "d109 = plt_border_width_Ref_Ref"
equation "d110 = plt_border_width_Ref_Ref"
equation "d111 = plt_border_width_Ref_Ref"
equation "d112 = plt_border_width_Ref_Ref"
equation "d115 = ( sw_size_Ref_Ref - 18 mm ) * 0.5"
equation "d116 = ( sw_size_Ref_Ref - 18 mm ) * 0.5"
equation "d117 = sw_size_Ref_Ref"
equation "d118 = sw_size_Ref_Ref"
equation "d119 = sw_size_Ref_Ref * 2"
equation "d120 = sw_size_Ref_Ref * 2"
equation "d121 = sw_size_Ref_Ref * 3"
equation "d122 = plt_border_width_Ref_Ref"
equation "d123 = plt_border_width_Ref_Ref"
equation "d124 = plt_border_width_Ref_Ref"
equation "d125 = plt_border_width_Ref_Ref"
equation "d126 = plt_border_width_Ref_Ref + ctrl_extension_width_Ref"
equation "d127 = plt_border_width_Ref_Ref"
equation "d128 = plt_border_width_Ref_Ref + ctrl_extension_width_Ref"
equation "d129 = plt_border_width_Ref_Ref"
equation "d130 = plt_border_width_Ref_Ref"
equation "d131 = plt_border_width_Ref_Ref + ctrl_extension_width_Ref"
equation "d132 = key_size_Ref_Ref + key_clearance_Ref_Ref"
equation "d133 = key_size_Ref_Ref + key_clearance_Ref_Ref"
equation "d134 = key_size_Ref_Ref + key_clearance_Ref_Ref"
equation "d135 = key_size_Ref_Ref + key_clearance_Ref_Ref"
equation "d136 = key_size_Ref_Ref + key_clearance_Ref_Ref"
equation "d137 = key_size_Ref_Ref + key_clearance_Ref_Ref"
equation "d138 = key_size_Ref_Ref + key_clearance_Ref_Ref"
equation "d139 = key_size_Ref_Ref + key_clearance_Ref_Ref"
equation "d140 = key_size_Ref_Ref + key_clearance_Ref_Ref"
equation "d141 = key_size_Ref_Ref + key_clearance_Ref_Ref"
equation "d142 = key_size_Ref_Ref + key_clearance_Ref_Ref"
equation "d143 = key_size_Ref_Ref + key_clearance_Ref_Ref"
equation "d144 = key_size_Ref_Ref + key_clearance_Ref_Ref"
equation "d145 = key_size_Ref_Ref + key_clearance_Ref_Ref"
equation "d146 = key_size_Ref_Ref + key_clearance_Ref_Ref"
equation "d147 = key_size_Ref_Ref + sw_size_Ref_Ref + key_clearance_Ref_Ref"
equation "d148 = key_size_Ref_Ref + sw_size_Ref_Ref + key_clearance_Ref_Ref"
equation "d149 = key_size_Ref_Ref + key_clearance_Ref_Ref"
equation "d150 = key_size_Ref_Ref + key_clearance_Ref_Ref"
equation "d151 = key_size_Ref_Ref + key_clearance_Ref_Ref"
equation "d154 = sw_size_Ref_Ref"
equation "d155 = -sw_size_Ref_Ref"
equation "d156 = key_size_Ref_Ref + sw_size_Ref_Ref * 2 + key_clearance_Ref_Ref"
equation "d157 = key_size_Ref_Ref + key_clearance_Ref_Ref"
equation "d158 = key_size_Ref_Ref + key_clearance_Ref_Ref"
equation "d159 = col_mid_offset_Ref_Ref"
equation "d163 = -sw_size_Ref_Ref"
equation "d167 = -sw_size_Ref_Ref"
equation "d170 = sw_size_Ref_Ref"
equation "d171 = -sw_size_Ref_Ref"
equation "d174 = sw_size_Ref_Ref"
equation "d175 = -sw_size_Ref_Ref"
equation "d179 = -sw_size_Ref_Ref"
equation "d182 = sw_size_Ref_Ref"
equation "d183 = sw_size_Ref_Ref"
equation "d184 = case_border_width_Ref_Ref"
equation "d185 = -top_inner_thickness_Ref_Ref"
equation "d187 = -case_top_thickness_Ref_Ref"
equation "d189 = top_align_mark_length_Ref_Ref"
equation "d190 = top_align_mark_length_Ref_Ref"
equation "d191 = top_align_mark_length_Ref_Ref"
equation "d192 = top_align_mark_length_Ref_Ref"
equation "d193 = top_align_mark_length_Ref_Ref"
equation "d194 = top_align_mark_length_Ref_Ref"
equation "d195 = plt_up_clearance_Ref_Ref - case_top_thickness_Ref_Ref + plt_thickness_Ref_Ref + pcb_thickness_Ref_Ref * 0.5"
equation "d197 = case_border_width_Ref_Ref * 1.75"
equation "d198 = thrins_diameter_Ref_Ref"
equation "d199 = case_border_width_Ref_Ref * 1.25"
equation "d200 = thrins_diameter_Ref_Ref"
equation "d201 = case_border_width_Ref_Ref * 1.75"
equation "d202 = thrins_diameter_Ref_Ref"
equation "d203 = case_border_width_Ref_Ref * 1.75"
equation "d204 = thrins_diameter_Ref_Ref"
equation "d205 = -thrins_depth_Ref_Ref"
equation "d208 = ( sw_size_Ref_Ref - key_size_Ref_Ref ) * 0.5 + plt_border_width_Ref_Ref"
equation "d209 = sw_size_Ref_Ref - plt_border_width_Ref_Ref * 2"
equation "d210 = ( sw_size_Ref_Ref - key_size_Ref_Ref ) * 0.5 + plt_border_width_Ref_Ref"
equation "d211 = ( sw_size_Ref_Ref - key_size_Ref_Ref ) * 0.5 + plt_border_width_Ref_Ref"
equation "d212 = ( sw_size_Ref_Ref - key_size_Ref_Ref ) * 0.5 + plt_border_width_Ref_Ref"
equation "d213 = ctrl_extension_width_Ref"
equation "d214 = plt_border_width_Ref_Ref + sw_size_Ref_Ref * 2 + plt_border_width_Ref_Ref"
equation "d215 = plt_border_width_Ref_Ref + ( sw_size_Ref_Ref - key_size_Ref_Ref ) * 0.5"
equation "d216 = plt_border_width_Ref_Ref + ( sw_size_Ref_Ref - key_size_Ref_Ref ) * 0.5"
equation "d232 = case_top_inner_border_side_fillet_Ref_Ref"
equation "d234 = case_top_inner_border_top_fillet_Ref_Ref"
equation "d235 = alignh_diameter_Ref_Ref"
equation "d237 = alignh_diameter_Ref_Ref"
equation "d238 = alignh_diameter_Ref_Ref"
equation "d240 = alignh_diameter_Ref_Ref"
equation "d241 = alignh_diameter_Ref_Ref"
equation "d242 = alignh_diameter_Ref_Ref"
equation "d243 = alignh_diameter_Ref_Ref"
equation "d244 = alignh_diameter_Ref_Ref"
equation "d245 = alignh_diameter_Ref_Ref"
equation "d246 = alignh_height_Ref_Ref"
equation "d249 = alignh_diameter_Ref_Ref * 0.5"
equation "d251 = key_fillet_Ref_Ref"
equation "d253 = case_side_fillet_Ref_Ref"
equation "d257 = case_top_fillet_Ref_Ref"
equation "pcase_max_length_Ref = sw_size_Ref_Ref * 8 + ( plt_border_width_Ref_Ref + case_border_width_Ref_Ref ) * 2 + ctrl_extension_width_Ref"

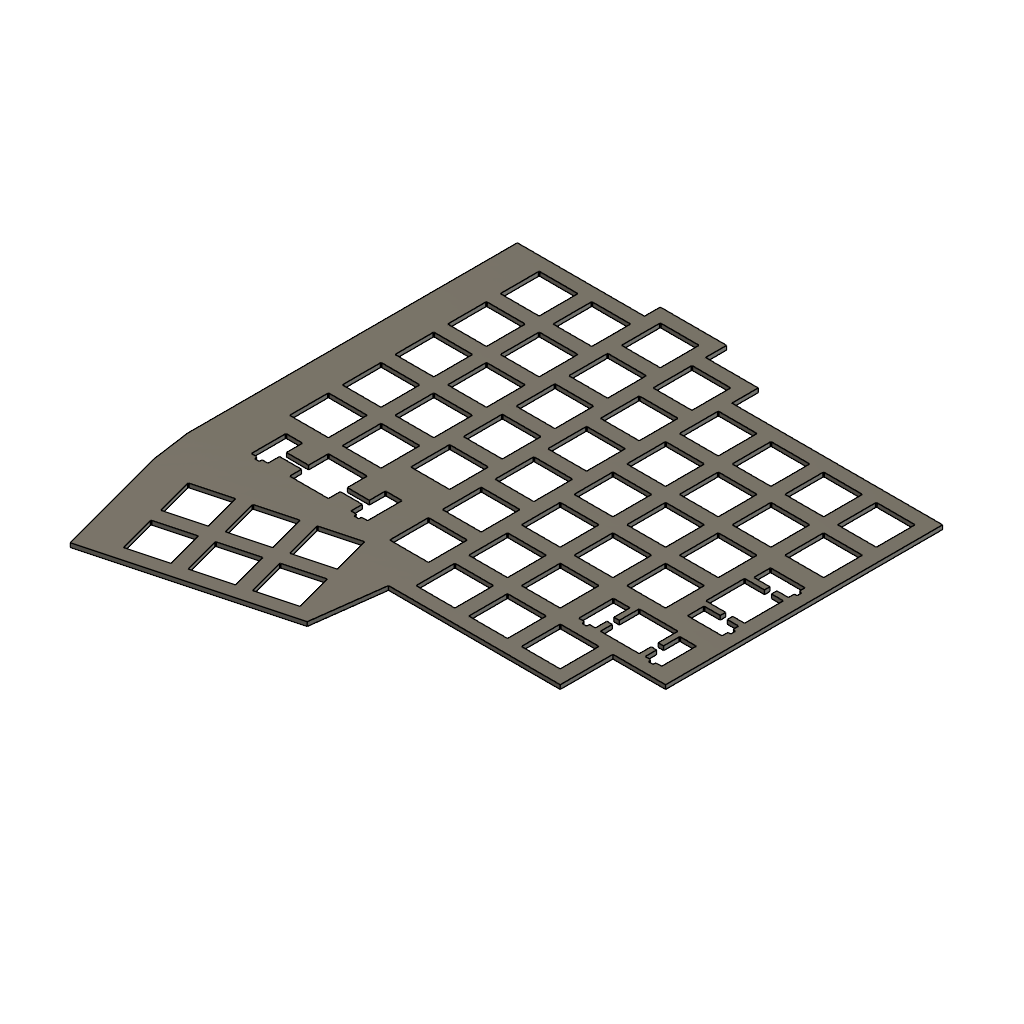
design "Plate (Pollux)" references "_Base (Pollux)"
part number: 2026-10-18-19-43-14-580
Autodesk Fusion 360 part; units mm, degrees
derive "Derived from _Base (Pollux)"